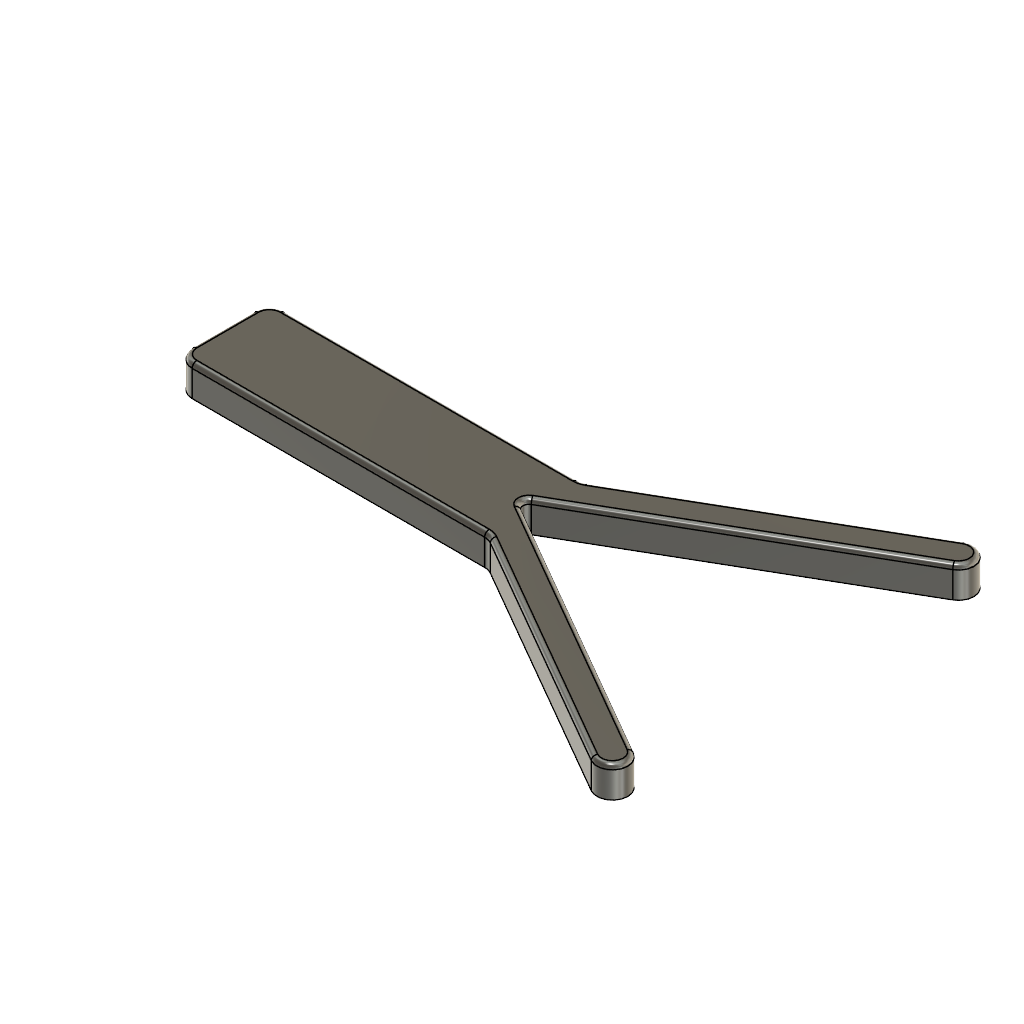
jar-opener_v0.1 (Autodesk Fusion 360 design; units mm, degrees)
part number: 2026-11-10-14-08-14-475
Autodesk Fusion 360 part; units mm, degrees
sketch "OpenerOutline" plane through (0, 0, 0) normal (0, 0, 1) x (1, 0, 0)
  line L0 (0, 1.75) -> (0, 22.5) construction
  line L1 (1.75, 0) -> (22.5, 0) construction
  line L2 (92, 64.6632) -> (92, 53.1162)
  line L3 (92, 53.1162) -> (0, 0)
  line L4 (0, 0) -> (92, -53.1162)
  line L5 (92, -53.1162) -> (92, -64.6632)
  line L6 (92, -64.6632) -> (5.9808, -15)
  line L7 (5.9808, -15) -> (-95, -15)
  line L8 (-95, -15) -> (-95, 15)
  line L9 (-95, 15) -> (5.9808, 15)
  line L10 (5.9808, 15) -> (92, 64.6632)
  line L11 (92, 64.6632) -> (92, 53.1162) construction
  dimension "d12" = 92
  dimension "d13" = 64.6632
  dimension "d14" = 53.1162
  dimension "d15" = 92
  dimension "d16" = 53.1162
  dimension "d17" = 92
  dimension "d18" = 64.6632
  dimension "d19" = 5.9808
  dimension "d20" = 15
  dimension "d21" = 95
  dimension "d22" = 15
  dimension "d23" = 95
  dimension "d24" = 15
  dimension "d25" = 5.9808
  dimension "d26" = 15
  constraint vertical L11
  constraint coincident L0 L3.end
  constraint coincident L1 L3.end
  measures "d12" horizontal distance of L3.end L2.start
  measures "d13" vertical distance of L3.end L2.start
  measures "d14" vertical distance of L3.end L2.end
  measures "d15" horizontal distance of L3.end L4.end
  measures "d16" vertical distance of L3.end L4.end
  measures "d17" horizontal distance of L3.end L5.end
  measures "d18" vertical distance of L3.end L5.end
  measures "d19" horizontal distance of L3.end L6.end
  measures "d20" vertical distance of L3.end L6.end
  measures "d21" horizontal distance of L3.end L7.end
  measures "d22" vertical distance of L3.end L7.end
  measures "d23" horizontal distance of L3.end L8.end
  measures "d24" vertical distance of L3.end L8.end
  measures "d25" horizontal distance of L3.end L9.end
  measures "d26" vertical distance of L3.end L9.end
extrude "Plate" add sketch "OpenerOutline" along normal blind 10
fillet "ApexRadius" radius 2 1 edges at (0, 0, 5)
fillet "CornerRadii" radius 5 8 edges at (92, 53.1162, 5) (5.9808, 15, 5) (92, 64.6632, 5) (92, -53.1162, 5) (92, -64.6632, 5) (5.9808, -15, 5) (-95, -15, 5) (-95, 15, 5)
fillet "TopComfortFillet" radius 1.5 196 edges at (-93.5355, 13.5355, 10) (-42.6795, 15, 10) (5.9351, 15.1704, 10) (45.8205, 38.0015, 10) (91.3301, 58.503, 10) (46.25, 26.7024, 10) (2, 0, 10) (46.25, -26.7024, 10) (91.3301, -58.503, 10) (45.8205, -38.0015, 10) (5.9351, -15.1704, 10) (-42.6795, -15, 10) (-93.5355, -13.5355, 10) (-95, 0, 10) (-42.6795, 15, 10) (-93.5355, 13.5355, 10) (-95, 0, 10) (-93.5355, -13.5355, 10) (-42.6795, -15, 10) (5.9351, -15.1704, 10) (45.8205, -38.0015, 10) (91.3301, -58.503, 10) (46.25, -26.7024, 10) (2, 0, 10) (46.25, 26.7024, 10) (91.3301, 58.503, 10) (45.8205, 38.0015, 10) (5.9351, 15.1704, 10) (-95, 0, 10) (-93.5355, -13.5355, 10) (-42.6795, -15, 10) (5.9351, -15.1704, 10) (45.8205, -38.0015, 10) (91.3301, -58.503, 10) (46.25, -26.7024, 10) (2, 0, 10) (46.25, 26.7024, 10) (91.3301, 58.503, 10) (45.8205, 38.0015, 10) (5.9351, 15.1704, 10) (-42.6795, 15, 10) (-93.5355, 13.5355, 10) (-93.5355, -13.5355, 10) (-95, 0, 10) (-93.5355, 13.5355, 10) (-42.6795, 15, 10) (5.9351, 15.1704, 10) (45.8205, 38.0015, 10) (91.3301, 58.503, 10) (46.25, 26.7024, 10) (2, 0, 10) (46.25, -26.7024, 10) (91.3301, -58.503, 10) (45.8205, -38.0015, 10) (5.9351, -15.1704, 10) (-42.6795, -15, 10) (-42.6795, -15, 10) (5.9351, -15.1704, 10) (45.8205, -38.0015, 10) (91.3301, -58.503, 10) (46.25, -26.7024, 10) (2, 0, 10) (46.25, 26.7024, 10) (91.3301, 58.503, 10) (45.8205, 38.0015, 10) (5.9351, 15.1704, 10) (-42.6795, 15, 10) (-93.5355, 13.5355, 10) (-95, 0, 10) (-93.5355, -13.5355, 10) (5.9351, -15.1704, 10) (-42.6795, -15, 10) (-93.5355, -13.5355, 10) (-95, 0, 10) (-93.5355, 13.5355, 10) (-42.6795, 15, 10) (5.9351, 15.1704, 10) (45.8205, 38.0015, 10) (91.3301, 58.503, 10) (46.25, 26.7024, 10) (2, 0, 10) (46.25, -26.7024, 10) (91.3301, -58.503, 10) (45.8205, -38.0015, 10) (45.8205, -38.0015, 10) (91.3301, -58.503, 10) (46.25, -26.7024, 10) (2, 0, 10) (46.25, 26.7024, 10) (91.3301, 58.503, 10) (45.8205, 38.0015, 10) (5.9351, 15.1704, 10) (-42.6795, 15, 10) (-93.5355, 13.5355, 10) (-95, 0, 10) (-93.5355, -13.5355, 10) (-42.6795, -15, 10) (5.9351, -15.1704, 10) (91.3301, -58.503, 10) (45.8205, -38.0015, 10) (5.9351, -15.1704, 10) (-42.6795, -15, 10) (-93.5355, -13.5355, 10) (-95, 0, 10) (-93.5355, 13.5355, 10) (-42.6795, 15, 10) (5.9351, 15.1704, 10) (45.8205, 38.0015, 10) (91.3301, 58.503, 10) (46.25, 26.7024, 10) (2, 0, 10) (46.25, -26.7024, 10) (46.25, -26.7024, 10) (2, 0, 10) (46.25, 26.7024, 10) (91.3301, 58.503, 10) (45.8205, 38.0015, 10) (5.9351, 15.1704, 10) (-42.6795, 15, 10) (-93.5355, 13.5355, 10) (-95, 0, 10) (-93.5355, -13.5355, 10) (-42.6795, -15, 10) (5.9351, -15.1704, 10) (45.8205, -38.0015, 10) (91.3301, -58.503, 10) (2, 0, 10) (46.25, -26.7024, 10) (91.3301, -58.503, 10) (45.8205, -38.0015, 10) (5.9351, -15.1704, 10) (-42.6795, -15, 10) (-93.5355, -13.5355, 10) (-95, 0, 10) (-93.5355, 13.5355, 10) (-42.6795, 15, 10) (5.9351, 15.1704, 10) (45.8205, 38.0015, 10) (91.3301, 58.503, 10) (46.25, 26.7024, 10) (46.25, 26.7024, 10) (91.3301, 58.503, 10) (45.8205, 38.0015, 10) (5.9351, 15.1704, 10) (-42.6795, 15, 10) (-93.5355, 13.5355, 10) (-95, 0, 10) (-93.5355, -13.5355, 10) (-42.6795, -15, 10) (5.9351, -15.1704, 10) (45.8205, -38.0015, 10) (91.3301, -58.503, 10) (46.25, -26.7024, 10) (2, 0, 10) (91.3301, 58.503, 10) (46.25, 26.7024, 10) (2, 0, 10) (46.25, -26.7024, 10) (91.3301, -58.503, 10) (45.8205, -38.0015, 10) (5.9351, -15.1704, 10) (-42.6795, -15, 10) (-93.5355, -13.5355, 10) (-95, 0, 10) (-93.5355, 13.5355, 10) (-42.6795, 15, 10) (5.9351, 15.1704, 10) (45.8205, 38.0015, 10) (45.8205, 38.0015, 10) (5.9351, 15.1704, 10) (-42.6795, 15, 10) (-93.5355, 13.5355, 10) (-95, 0, 10) (-93.5355, -13.5355, 10) (-42.6795, -15, 10) (5.9351, -15.1704, 10) (45.8205, -38.0015, 10) (91.3301, -58.503, 10) (46.25, -26.7024, 10) (2, 0, 10) (46.25, 26.7024, 10) (91.3301, 58.503, 10) (5.9351, 15.1704, 10) (45.8205, 38.0015, 10) (91.3301, 58.503, 10) (46.25, 26.7024, 10) (2, 0, 10) (46.25, -26.7024, 10) (91.3301, -58.503, 10) (45.8205, -38.0015, 10) (5.9351, -15.1704, 10) (-42.6795, -15, 10) (-93.5355, -13.5355, 10) (-95, 0, 10) (-93.5355, 13.5355, 10) (-42.6795, 15, 10)
equation "cap_max = 82 mm" comment "Largest cap the jaw seats: 82 mm, largest regular twist-off lug cap in a closure maker's size list (38-82 mm)"
equation "cap_min = 28 mm" comment "Smallest cap: 28 mm PCO 1881 bottle neck finish (cap outer diameter not published - slightly larger)"
equation "v_half = 30 deg" comment "V half-angle. A cap of diameter D seats D/(2 sin(v_half)) from the apex; 30 deg -> seat distance = D (design choice)"
equation "jaw_len = cap_max / ( 2 * sin(v_half) ) + 10 mm" comment "V depth: seat of the largest cap + 10 mm of jaw beyond it"
equation "jaw_wall = 10 mm" comment "Jaw arm thickness measured perpendicular to the V wall (design estimate; checked in FE)"
equation "handle_len = 95 mm" comment "Handle length = ANSUR II hand breadth + 8-9 mm, rounded to 5 mm (M: all-subjects median 86 mm)"
equation "handle_w = 30 mm" comment "Handle width (design estimate)"
equation "plate_t = 10 mm" comment "Plate thickness = height of jaw contact on the cap skirt (design estimate)"
equation "apex_r = 2 mm" comment "Radius at the V apex (removes a sharp inside corner)"
equation "corner_r = 5 mm" comment "Radius on outer vertical corners"
equation "top_r = 1.5 mm" comment "Comfort fillet around the top face (bed side stays sharp for adhesion)"
equation "d12 = abs(jaw_len)"
equation "d13 = abs(( jaw_len * tan(v_half) + jaw_wall / cos(v_half) ))"
equation "d14 = abs(jaw_len * tan(v_half))"
equation "d15 = abs(jaw_len)"
equation "d16 = abs(-jaw_len * tan(v_half))"
equation "d17 = abs(jaw_len)"
equation "d18 = abs(-( jaw_len * tan(v_half) + jaw_wall / cos(v_half) ))"
equation "d19 = abs(( ( handle_w / 2 - jaw_wall / cos(v_half) ) / tan(v_half) ))"
equation "d20 = abs(-handle_w / 2)"
equation "d21 = abs(-handle_len)"
equation "d22 = abs(-handle_w / 2)"
equation "d23 = abs(-handle_len)"
equation "d24 = abs(handle_w / 2)"
equation "d25 = abs(( ( handle_w / 2 - jaw_wall / cos(v_half) ) / tan(v_half) ))"
equation "d26 = abs(handle_w / 2)"
equation "d27 = plate_t"
equation "d30 = apex_r"
equation "d32 = corner_r"
equation "d34 = top_r"
named bodies: "JarOpener"
